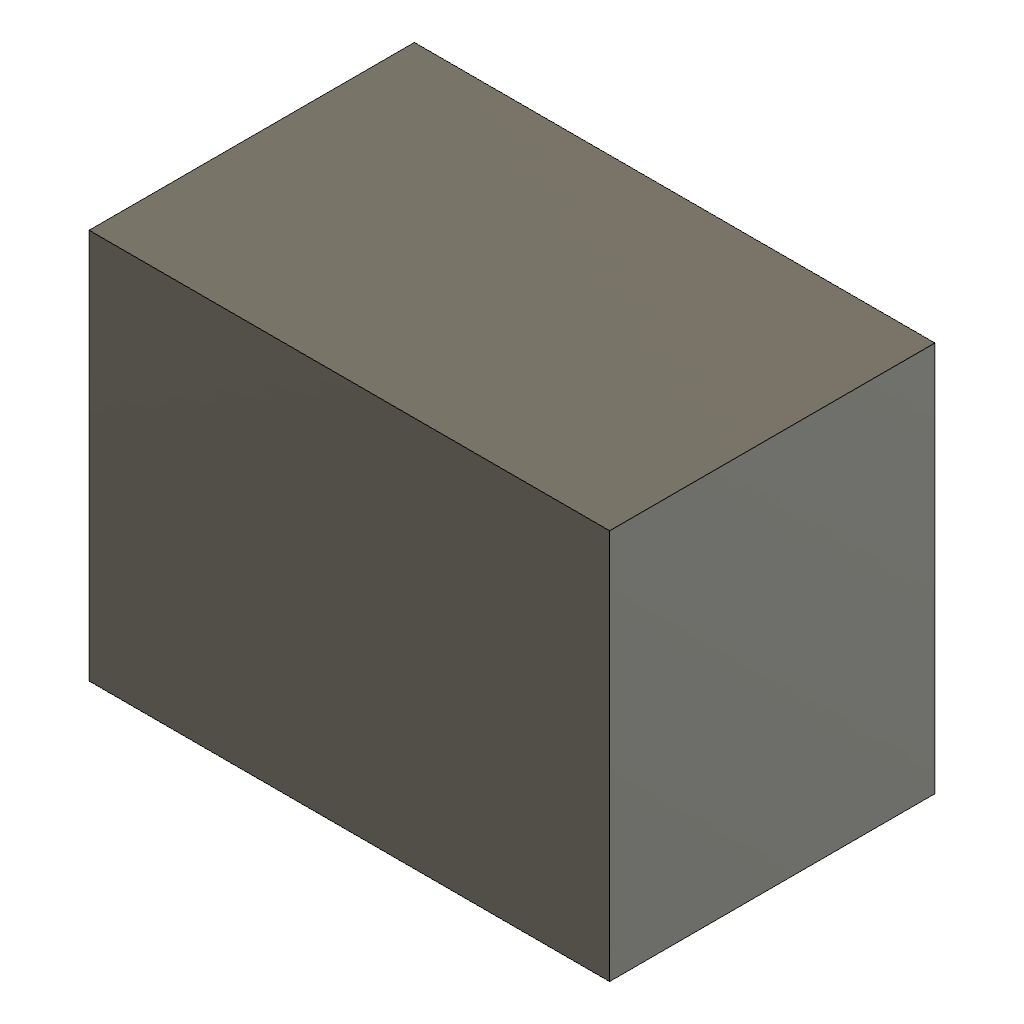
OrdinaryRectangleSnapshot (Autodesk Fusion 360 design; units mm, degrees)
part number: 2026-10-21-11-20-37-863
Autodesk Fusion 360 part; units mm, degrees
sketch "ThinProbeSource" plane through (0, 0, 0) normal (0, 0, 1) x (1, 0, 0)
  line L0 (0, 0) -> (40, 0)
  line L1 (40, 0) -> (40, 30)
  line L2 (40, 30) -> (0, 30)
  line L3 (0, 30) -> (0, 0)
extrude "ProbeOrdinaryExtrudeControl" add sketch "ThinProbeSource" along normal blind 25
